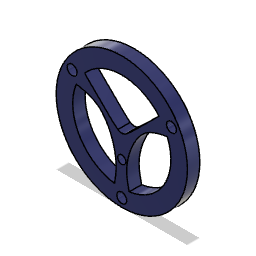
TOPPLATE v4 v1 (Autodesk Fusion 360 design; units mm, degrees)
Autodesk Fusion 360 part; units mm, degrees
sketch "Sketch1" plane through (0, 0, 0) normal (0, 0, 1) x (1, 0, 0)
  circle A0 centre (60, 34.641) radius 6
  circle A1 centre (-60, 34.641) radius 6
  circle A2 centre (0, -69.282) radius 6
  circle A3 centre (0, 0) radius 79.282
  circle A4 centre (0, 0) radius 59.282
  circle A5 centre (0, -29.282) radius 5
  line L0 (0, 45) -> (0, 30) construction
  spline S0 degree 5 poles (-8.8874, -58.6121) (-7.2243, -50.1744) (-5, -35) (-7.6746, -13.3534) (-19.3104, 7.716) (-32.2776, 18.3338) (-54.9906, 22.1449) knots 0.090629 0.090629 0.090629 0.090629 0.090629 0.090629 0.5 0.906539 0.906539 0.906539 0.906539 0.906539 0.906539
  line L1 (-8.8874, -58.6121) -> (-7.2243, -50.1744)
  line L2 (-7.2243, -50.1744) -> (-5, -35)
  line L3 (-5, -35) -> (-7.6746, -13.3534)
  line L4 (-7.6746, -13.3534) -> (-19.3104, 7.716)
  line L5 (-19.3104, 7.716) -> (-32.2776, 18.3338)
  line L6 (-32.2776, 18.3338) -> (-54.9906, 22.1449)
  spline S1 degree 5 poles (8.8874, -58.6121) (7.2243, -50.1744) (2.4438, -34.5181) (7.6746, -13.3534) (19.3104, 7.716) (32.2776, 18.3338) (54.9906, 22.1449) knots 0.090629 0.090629 0.090629 0.090629 0.090629 0.090629 0.5 0.906539 0.906539 0.906539 0.906539 0.906539 0.906539
  line L7 (8.8874, -58.6121) -> (7.2243, -50.1744)
  line L8 (7.2243, -50.1744) -> (2.4438, -34.5181)
  line L9 (2.4438, -34.5181) -> (7.6746, -13.3534)
  line L10 (7.6746, -13.3534) -> (19.3104, 7.716)
  line L11 (19.3104, 7.716) -> (32.2776, 18.3338)
  line L12 (32.2776, 18.3338) -> (54.9906, 22.1449)
  spline S2 degree 5 poles (-44.8829, 38.7283) (-36.423, 29.6291) (-27.6537, 21.9182) (-20.0232, 14.1428) (-12.7228, 5.6879) (-4.7422, -0.186) knots 0.200528 0.200528 0.200528 0.200528 0.200528 0.200528 0.704869 0.704869 0.704869 0.704869 0.704869 0.704869
  spline S3 degree 5 poles (44.8829, 38.7283) (36.423, 29.6291) (27.6537, 21.9182) (20.0232, 14.1428) (12.7228, 5.6879) (4.7422, -0.186) knots 0.200528 0.200528 0.200528 0.200528 0.200528 0.200528 0.704869 0.704869 0.704869 0.704869 0.704869 0.704869
  arc A6 (-4.7422, -0.186) -> (4.7422, -0.186) centre (0, 6.2569) ccw
  line L13 (-44.8829, 38.7283) -> (-36.423, 29.6291)
  line L14 (-36.423, 29.6291) -> (-27.6537, 21.9182)
  line L15 (-27.6537, 21.9182) -> (-20.0232, 14.1428)
  line L16 (-20.0232, 14.1428) -> (-12.7228, 5.6879)
  line L17 (-12.7228, 5.6879) -> (-4.7422, -0.186)
  line L18 (44.8829, 38.7283) -> (36.423, 29.6291)
  line L19 (36.423, 29.6291) -> (27.6537, 21.9182)
  line L20 (27.6537, 21.9182) -> (20.0232, 14.1428)
  line L21 (20.0232, 14.1428) -> (12.7228, 5.6879)
  line L22 (12.7228, 5.6879) -> (4.7422, -0.186)
  point P0 (0, -29.282)
  dimension "d47_3" = 12
  dimension "d69_2" = 40
  dimension "d70_1" = 10
  dimension "d71_1" = 8
  constraint coincident A3.centre A4.centre
  constraint coincident P0 A5.centre
  constraint vertical L0
  constraint coincident A4 S2.start
  constraint coincident A4 S0.end
  constraint coincident A4 S0.start
  constraint coincident A4 S1.start
  constraint coincident A4 S1.end
  constraint coincident A4 S3.start
  constraint tangent S2 A6
  constraint tangent S3 A6
  measures "d47_3" diameter of A0
  measures "d69_2" distance of A2.centre P0
  measures "d70_1" diameter of A5
  measures "d71_1" radius of A6
extrude "Extrude5" add sketch "Sketch1" along normal blind 15 contours A3 | A4 A5 L1 L2 L3 L4 L5 L6 S1 L8 L9 L10 L11 L12 S2 S3 A6 L13 L14 L16 L17 L18 L19 L21 L22 | A5 S1 L8 L9 L10 L11 L12 | S3 L18 L19 | S0 L1 L2 L3 L4 L5 L6 | S2 L13 L14 | S3 L21 L22 | S2 L16 L17
